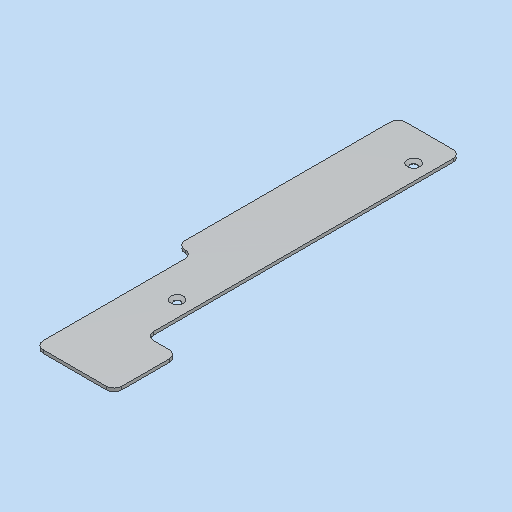
# Autodesk Inventor part: SE0004AN000_G01_190
Saved by Autodesk Inventor 2023.3 (Build 273359000, 359)
## iProperties
RuleStatus: InUse
Created: 2022-03-14
Part Number: SE0004AN000_G01_190
Material: 3.3535 AlMg3 - AW 5754 (Blech)
Description: =<RBPARTNOTITLE2>
Document SubType Name: Blech
Designer: frt9bw
Mass: 50.3065 g
Surface Area: 198.947 cm^2
Volume: 18.6389 cm^3
Density: 2.699 g/cm^3
Sheet Metal Rule: Standard_mm
Appearance: Aluminium AnP
AnP_Kategorie: 1
AnP_Material: =<Material>
MaxAbmaße: 2 x 240 x 60 (FM)
AnP_TemplVers: 20200821
RBDOCUMENTTYPE: DRF
RBDOCUMENTVERSION: 00
RBDRAWINGMAINSCALE: 1:1
RBDRAWINGMISSINGSPEC: --
RBDRAWINGVOLUME: --
RBDSV1: 0850
RBGBEDGESIN1: +0,5
RBGBEDGESIN2: +0,2
RBGBEDGESOUT1: -0,3
RBGBEDGESOUT2: -0,1
RBMATERIAL: =<Material>
RBMATMEETS: --
RBMATNO: =<Part Number>
RBPARTMADEOF: 2 x 240 x 60 (FM)
RBPARTNO: SIEHE MNR
RBPARTNOTITLE1: manufactured part
RBPARTNOTITLE2: Anfertigungsteil
RBPARTSAFETYINDICATOR: --
RBSURFACE: --
RBSURFACE2: eloxiert E6/EV1 aluminiumfarbig
RBZEDGESNORM: ISO13715:2002-06
RBZGENDIMCLASS: m
RBZGENDIMNORM: ISO 2768-1:1989-11
RBZGENGEOCLASS: H
RBZGENGEONORM: ISO 2768-2:1989-11
RBZSURFACENORM: ISO13D2:2002-02
RBZTOLERANCENORM: ISO 14405-1:2010-12
Author: frt9bw
Keywords: =<RBPARTMADEOF>
Comments: =<RBSURFACE2>
Revision Number: 01
Autodesk Inventor part; units mm, degrees
ref_plane "YZ Plane" through (0, 0, 0) normal (1, 0, 0) x (0, 1, 0)
ref_plane "XZ Plane" through (0, 0, 0) normal (0, 1, 0) x (-1, 0, 0)
ref_plane "XY Plane" through (0, 0, 0) normal (0, 0, 1) x (1, 0, 0)
sketch "Skizze1" plane through (0, 0, 0) normal (0, 0, 1) x (1, 0, 0)
  line L0 (0, 0) -> (40, 0)
  line L1 (40, 0) -> (40, 240)
  line L2 (40, 240) -> (0, 240)
  line L3 (0, 240) -> (0, 0)
  dimension "d0" = 40
  dimension "d1" = 240
  measures "d0" distance of L2.end L1.end
  measures "d1" distance of L1.end L0.end
extrude "Grobblech1" add sketch "Skizze1" along normal blind 2
sketch "Skizze2" plane through (0, 0, 2) normal (0, 0, 1) x (1, 0, 0)
  line L0 (0, 0) -> (0, 240) projected
  line L1 (40, 0) -> (0, 0) projected
  line L2 (40, 240) -> (40, 0) projected
  line L3 (0, 240) -> (40, 240) projected
  line L4 (0, 0) -> (10, 0)
  line L5 (10, 0) -> (10, 100)
  line L6 (10, 100) -> (0, 100)
  line L7 (0, 100) -> (0, 0)
  dimension "d3" = 10
  dimension "d4" = 100
  constraints: 8 end point, 2 parallel, 1 horizontal, 1 perpendicular
  measures "d3" distance of L5.end L6.end
  measures "d4" distance of L4.end L5.end
extrude "Extrusion1" cut sketch "Skizze2" against normal through all contours L0 L6 L5 L1
sketch "Skizze3" plane through (40, 0, 0) normal (1, 0, 0) x (0, 0, -1)
  line L0 (-2, 240) -> (-2, 0) projected
  line L1 (0, 0) -> (-2, 0) projected
  line L2 (0, 0) -> (0, 240) projected
  line L3 (0, 240) -> (-2, 240) projected
  line L4 (-2, 0) -> (0, 0)
  line L5 (0, 0) -> (0, 40)
  line L6 (0, 40) -> (-2, 40)
  line L7 (-2, 40) -> (-2, 0)
  dimension "d7" = 40
  constraints: 8 end point, 2 parallel, 1 horizontal, 1 perpendicular, 1 point on line
  measures "d7" distance between parallel lines of L6 L1
extrude "Extrusion2" add sketch "Skizze3" along normal blind 20 contours L6 L2 L1 L0
sketch "Skizze4" plane through (0, 0, 2) normal (0, 0, 1) x (1, 0, 0)
  line L0 (40, 240) -> (40, 40) projected
  line L1 (0, 240) -> (40, 240) projected
  point P0 (0, 0)
  point P1 (30, 220)
  point P2 (30, 70)
  dimension "d10" = 10
  dimension "d11" = 20
  dimension "d12" = 150
  constraints: 1 vertical alignment
  measures "d10" distance from line of L0 point (30, 220)
  measures "d11" distance from line of L1 point (30, 220)
  measures "d12" distance of point (30, 220) point (30, 70)
hole "Bohrung1" at (30, 220, 2) at (30, 70, 2) direction (0, 0, -1) diameter 4.5 depth 2 tip angle 118 countersink diameter 8 countersink angle 90
fillet "Rundung1" radius 5 8 edges at (60, 40, 1) (60, 0, 1) (10, 0, 1) (10, 100, 1) (0, 100, 1) (40, 240, 1) (0, 240, 1) (40, 40, 1)
equation "\"d2\" = Stärke"
equation "\"Biegeradius\" = Stärke"
equation "\"BreiteBiegungsfreistellung\" = Stärke"
equation "\"TiefeBiegungsfreistellung\" = 0.5 * Stärke"
equation "\"GrößeEckenfreistellung\" = 4 * Stärke"
equation "\"MinimalRest\" = 2 * Stärke"
equation "\"Übergangsradius\" = Biegeradius"
equation "\"JacobiRadiusGröße\" = Biegeradius"
equation "\"Abstandsgröße\" = Stärke"
equation "\"Stärke\" = 2"
